Autodesk Fusion 360 part; units mm, degrees
(part 3 of 7)
ref_plane "WorkPlane1" through (0, 0, 65.5) normal (0, 0, 1) x (1, 0, 0) in component "front right crossmember backing plate"
sketch "New stock profile (16)" plane through (0, 0, 65.5) normal (0, 0, 1) x (1, 0, 0) in component "front right crossmember backing plate"
  line L0 (103.6, -314.6) -> (154.4, -314.6)
  line L1 (154.4, -314.6) -> (154.4, -308.25)
  line L2 (154.4, -308.25) -> (103.6, -308.25)
  line L3 (103.6, -308.25) -> (103.6, -314.6)
extrude "New 1'''''''''''''''" add sketch "New stock profile (16)" along normal blind 63.5 separate body makes body 142 in component "front right crossmember backing plate"
ref_plane "WorkPlane1" through (0, 0, 65.5) normal (0, 0, 1) x (1, 0, 0) in component "front left crossmember backing plate"
sketch "New stock profile (17)" plane through (0, 0, 65.5) normal (0, 0, 1) x (1, 0, 0) in component "front left crossmember backing plate"
  line L0 (103.6, 308.25) -> (154.4, 308.25)
  line L1 (154.4, 308.25) -> (154.4, 314.6)
  line L2 (154.4, 314.6) -> (103.6, 314.6)
  line L3 (103.6, 314.6) -> (103.6, 308.25)
extrude "New 1''''''''''''''''" add sketch "New stock profile (17)" along normal blind 63.5 separate body makes body 143 in component "front left crossmember backing plate"
ref_plane "WorkPlane1" through (0, 0, -8.47) normal (0, 0, 1) x (1, 0, 0) in component "front left module tab spacer 1"
sketch "New stock profile (18)" plane through (0, 0, -8.47) normal (0, 0, 1) x (1, 0, 0) in component "front left module tab spacer 1"
  line L0 (-20.7, -14.55) -> (15, -14.55)
  line L1 (15, -14.55) -> (15, 11.55)
  line L2 (15, 11.55) -> (-20.7, 11.55)
  line L3 (-20.7, 11.55) -> (-20.7, -14.55)
extrude "New 1'''''''''''''''''" add sketch "New stock profile (18)" along normal blind 50.8 separate body makes body 144 in component "front left module tab spacer 1"
ref_plane "WorkPlane2" through (0, 0, -10.22) normal (0, 0, 1) x (1, 0, 0) in component "front left module tab spacer 1"
sketch "Cut stock profile (17)" plane through (0, 0, -10.22) normal (0, 0, 1) x (1, 0, 0) in component "front left module tab spacer 1"
  circle A0 centre (9.85, -6.3) radius 2.65
extrude "Cut 2''''''''" cut sketch "Cut stock profile (17)" along normal blind 54 bodies 144 in component "front left module tab spacer 1"
ref_plane "WorkPlane3" through (0, 0, -10.22) normal (0, 0, 1) x (1, 0, 0) in component "front left module tab spacer 1"
sketch "Cut stock profile (1) (6)" plane through (0, 0, -10.22) normal (0, 0, 1) x (1, 0, 0) in component "front left module tab spacer 1"
  circle A0 centre (-15.55, -6.3) radius 2.65
extrude "Cut 3" cut sketch "Cut stock profile (1) (6)" along normal blind 54 bodies 144 in component "front left module tab spacer 1"
ref_plane "WorkPlane4" through (0, 12.55, 0) normal (0, 1, 0) x (0, 0, 1) in component "front left module tab spacer 1"
sketch "Cut stock profile (2) (6)" plane through (0, 12.55, 0) normal (0, 1, 0) x (1, 0, 0) in component "front left module tab spacer 1"
  circle A0 centre (-2.85, -5.78) radius 3.25
extrude "Cut 4" [suppressed] in component "left perimeter tube"
extrude "Extrude7" cut sketch "Cut stock profile (2) (6)" against normal blind 28.1 bodies 144 in component "front left module tab spacer 1"
ref_plane "WorkPlane5" through (0, 12.55, 0) normal (0, 1, 0) x (0, 0, 1) in component "front left module tab spacer 1"
sketch "Cut stock profile (3) (4)" plane through (0, 12.55, 0) normal (0, 1, 0) x (1, 0, 0) in component "front left module tab spacer 1"
  circle A0 centre (-2.85, -26.78) radius 3.25
extrude "Cut 5 (1)" [suppressed] in component "left perimeter tube"
extrude "Extrude8" cut sketch "Cut stock profile (3) (4)" against normal blind 28.1 bodies 144 in component "front left module tab spacer 1"
ref_plane "WorkPlane6" through (0, 12.55, 0) normal (0, 1, 0) x (0, 0, 1) in component "front left module tab spacer 1"
sketch "Cut stock profile (4) (4)" plane through (0, 12.55, 0) normal (0, 1, 0) x (1, 0, 0) in component "front left module tab spacer 1"
  circle A0 centre (9.2, -16.93) radius 5.35
extrude "Cut 6" [suppressed] in component "left perimeter tube"
extrude "Extrude9" cut sketch "Cut stock profile (4) (4)" against normal blind 28.1 bodies 144 in component "front left module tab spacer 1"
ref_plane "WorkPlane7" through (0, 12.55, 0) normal (0, 1, 0) x (0, 0, 1) in component "front left module tab spacer 1"
sketch "Cut stock profile (5) (2)" plane through (0, 12.55, 0) normal (0, 1, 0) x (1, 0, 0) in component "front left module tab spacer 1"
  circle A0 centre (-14.9, -16.93) radius 5.35
extrude "Cut 7" [suppressed] in component "left perimeter tube"
extrude "Extrude10" cut sketch "Cut stock profile (5) (2)" against normal blind 28.1 bodies 144 in component "front left module tab spacer 1"
ref_plane "WorkPlane1" through (0, 0, -8.47) normal (0, 0, 1) x (1, 0, 0) in component "front left module tab spacer 2"
sketch "New stock profile (19)" plane through (0, 0, -8.47) normal (0, 0, 1) x (1, 0, 0) in component "front left module tab spacer 2"
  line L0 (-14.55, -20.7) -> (11.55, -20.7)
  line L1 (11.55, -20.7) -> (11.55, 15)
  line L2 (11.55, 15) -> (-14.55, 15)
  line L3 (-14.55, 15) -> (-14.55, -20.7)
extrude "New 1''''''''''''''''''" add sketch "New stock profile (19)" along normal blind 50.8 separate body makes body 145 in component "front left module tab spacer 2"
ref_plane "WorkPlane2" through (0, 0, -10.22) normal (0, 0, 1) x (1, 0, 0) in component "front left module tab spacer 2"
sketch "Cut stock profile (18)" plane through (0, 0, -10.22) normal (0, 0, 1) x (1, 0, 0) in component "front left module tab spacer 2"
  circle A0 centre (-6.3, 9.85) radius 2.65
extrude "Cut 2'''''''''" cut sketch "Cut stock profile (18)" along normal blind 54 bodies 145 in component "front left module tab spacer 2"
ref_plane "WorkPlane3" through (0, 0, -10.22) normal (0, 0, 1) x (1, 0, 0) in component "front left module tab spacer 2"
sketch "Cut stock profile (1) (7)" plane through (0, 0, -10.22) normal (0, 0, 1) x (1, 0, 0) in component "front left module tab spacer 2"
  circle A0 centre (-6.3, -15.55) radius 2.65
extrude "Cut 3'" cut sketch "Cut stock profile (1) (7)" along normal blind 54 bodies 145 in component "front left module tab spacer 2"
ref_plane "WorkPlane4" through (12.55, 0, 0) normal (1, 0, 0) x (0, 1, 0) in component "front left module tab spacer 2"
sketch "Cut stock profile (2) (7)" plane through (12.55, 0, 0) normal (1, 0, 0) x (0, 0, -1) in component "front left module tab spacer 2"
  circle A0 centre (-5.78, -2.85) radius 3.25
extrude "Cut 4'" [suppressed] in component "left front return"
extrude "Extrude7'" cut sketch "Cut stock profile (2) (7)" against normal blind 28.1 bodies 145 in component "front left module tab spacer 2"
ref_plane "WorkPlane5" through (12.55, 0, 0) normal (1, 0, 0) x (0, 1, 0) in component "front left module tab spacer 2"
sketch "Cut stock profile (3) (5)" plane through (12.55, 0, 0) normal (1, 0, 0) x (0, 0, -1) in component "front left module tab spacer 2"
  circle A0 centre (-26.78, -2.85) radius 3.25
extrude "Cut 5" [suppressed] in component "left front return"
extrude "Extrude8'" cut sketch "Cut stock profile (3) (5)" against normal blind 28.1 bodies 145 in component "front left module tab spacer 2"
ref_plane "WorkPlane6" through (12.55, 0, 0) normal (1, 0, 0) x (0, 1, 0) in component "front left module tab spacer 2"
sketch "Cut stock profile (4) (5)" plane through (12.55, 0, 0) normal (1, 0, 0) x (0, 0, -1) in component "front left module tab spacer 2"
  circle A0 centre (-16.93, 9.2) radius 5.35
extrude "Cut 6'" [suppressed] in component "left front return"
extrude "Extrude9'" cut sketch "Cut stock profile (4) (5)" against normal blind 28.1 bodies 145 in component "front left module tab spacer 2"
ref_plane "WorkPlane7" through (12.55, 0, 0) normal (1, 0, 0) x (0, 1, 0) in component "front left module tab spacer 2"
sketch "Cut stock profile (5) (3)" plane through (12.55, 0, 0) normal (1, 0, 0) x (0, 0, -1) in component "front left module tab spacer 2"
  circle A0 centre (-16.93, -14.9) radius 5.35
extrude "Cut 7'" [suppressed] in component "left front return"
extrude "Extrude10'" cut sketch "Cut stock profile (5) (3)" against normal blind 28.1 bodies 145 in component "front left module tab spacer 2"
ref_plane "WorkPlane1" through (0, 0, -8.47) normal (0, 0, 1) x (1, 0, 0) in component "front right module tab spacer 1"
sketch "New stock profile (20)" plane through (0, 0, -8.47) normal (0, 0, 1) x (1, 0, 0) in component "front right module tab spacer 1"
  line L0 (-14.55, -15) -> (11.55, -15)
  line L1 (11.55, -15) -> (11.55, 20.7)
  line L2 (11.55, 20.7) -> (-14.55, 20.7)
  line L3 (-14.55, 20.7) -> (-14.55, -15)
extrude "New 1'''''''''''''''''''" add sketch "New stock profile (20)" along normal blind 50.8 separate body makes body 146 in component "front right module tab spacer 1"
ref_plane "WorkPlane2" through (0, 0, -10.22) normal (0, 0, 1) x (1, 0, 0) in component "front right module tab spacer 1"
sketch "Cut stock profile (19)" plane through (0, 0, -10.22) normal (0, 0, 1) x (1, 0, 0) in component "front right module tab spacer 1"
  circle A0 centre (-6.3, -9.85) radius 2.65
extrude "Cut 2''''''''''" cut sketch "Cut stock profile (19)" along normal blind 54 bodies 146 in component "front right module tab spacer 1"
ref_plane "WorkPlane3" through (0, 0, -10.22) normal (0, 0, 1) x (1, 0, 0) in component "front right module tab spacer 1"
sketch "Cut stock profile (1) (8)" plane through (0, 0, -10.22) normal (0, 0, 1) x (1, 0, 0) in component "front right module tab spacer 1"
  circle A0 centre (-6.3, 15.55) radius 2.65
extrude "Cut 3''" cut sketch "Cut stock profile (1) (8)" along normal blind 54 bodies 146 in component "front right module tab spacer 1"
ref_plane "WorkPlane4" through (12.55, 0, 0) normal (1, 0, 0) x (0, 1, 0) in component "front right module tab spacer 1"
sketch "Cut stock profile (2) (8)" plane through (12.55, 0, 0) normal (1, 0, 0) x (0, 0, -1) in component "front right module tab spacer 1"
  circle A0 centre (-5.78, 2.85) radius 3.25
extrude "Cut 4''" [suppressed] in component "right front return"
extrude "Extrude7''" cut sketch "Cut stock profile (2) (8)" against normal blind 28.1 bodies 146 in component "front right module tab spacer 1"
ref_plane "WorkPlane5" through (12.55, 0, 0) normal (1, 0, 0) x (0, 1, 0) in component "front right module tab spacer 1"
sketch "Cut stock profile (3) (6)" plane through (12.55, 0, 0) normal (1, 0, 0) x (0, 0, -1) in component "front right module tab spacer 1"
  circle A0 centre (-26.78, 2.85) radius 3.25
extrude "Cut 5'" [suppressed] in component "right front return"
extrude "Extrude8''" cut sketch "Cut stock profile (3) (6)" against normal blind 28.1 bodies 146 in component "front right module tab spacer 1"
ref_plane "WorkPlane6" through (12.55, 0, 0) normal (1, 0, 0) x (0, 1, 0) in component "front right module tab spacer 1"
sketch "Cut stock profile (4) (6)" plane through (12.55, 0, 0) normal (1, 0, 0) x (0, 0, -1) in component "front right module tab spacer 1"
  circle A0 centre (-16.93, -9.2) radius 5.35
extrude "Cut 6''" [suppressed] in component "right front return"
extrude "Extrude9''" cut sketch "Cut stock profile (4) (6)" against normal blind 28.1 bodies 146 in component "front right module tab spacer 1"
ref_plane "WorkPlane7" through (12.55, 0, 0) normal (1, 0, 0) x (0, 1, 0) in component "front right module tab spacer 1"
sketch "Cut stock profile (5) (4)" plane through (12.55, 0, 0) normal (1, 0, 0) x (0, 0, -1) in component "front right module tab spacer 1"
  circle A0 centre (-16.93, 14.9) radius 5.35
extrude "Cut 7''" [suppressed] in component "right front return"
extrude "Extrude10''" cut sketch "Cut stock profile (5) (4)" against normal blind 28.1 bodies 146 in component "front right module tab spacer 1"
ref_plane "WorkPlane1" through (0, 0, -8.47) normal (0, 0, 1) x (1, 0, 0) in component "front right module tab spacer 2"
sketch "New stock profile (21)" plane through (0, 0, -8.47) normal (0, 0, 1) x (1, 0, 0) in component "front right module tab spacer 2"
  line L0 (-20.7, -11.55) -> (15, -11.55)
  line L1 (15, -11.55) -> (15, 14.55)
  line L2 (15, 14.55) -> (-20.7, 14.55)
  line L3 (-20.7, 14.55) -> (-20.7, -11.55)
extrude "New 1''''''''''''''''''''" add sketch "New stock profile (21)" along normal blind 50.8 separate body makes body 147 in component "front right module tab spacer 2"
ref_plane "WorkPlane2" through (0, 0, -10.22) normal (0, 0, 1) x (1, 0, 0) in component "front right module tab spacer 2"
sketch "Cut stock profile (20)" plane through (0, 0, -10.22) normal (0, 0, 1) x (1, 0, 0) in component "front right module tab spacer 2"
  circle A0 centre (9.85, 6.3) radius 2.65
extrude "Cut 2'''''''''''" cut sketch "Cut stock profile (20)" along normal blind 54 bodies 147 in component "front right module tab spacer 2"
ref_plane "WorkPlane3" through (0, 0, -10.22) normal (0, 0, 1) x (1, 0, 0) in component "front right module tab spacer 2"
sketch "Cut stock profile (1) (9)" plane through (0, 0, -10.22) normal (0, 0, 1) x (1, 0, 0) in component "front right module tab spacer 2"
  circle A0 centre (-15.55, 6.3) radius 2.65
extrude "Cut 3'''" cut sketch "Cut stock profile (1) (9)" along normal blind 54 bodies 147 in component "front right module tab spacer 2"
ref_plane "WorkPlane4" through (0, -12.55, 0) normal (0, 1, 0) x (0, 0, 1) in component "front right module tab spacer 2"
sketch "Cut stock profile (2) (9)" plane through (0, -12.55, 0) normal (0, 1, 0) x (1, 0, 0) in component "front right module tab spacer 2"
  circle A0 centre (-2.85, -5.78) radius 3.25
extrude "Cut 4'''" [suppressed] in component "right perimeter tube"
extrude "Extrude7'''" cut sketch "Cut stock profile (2) (9)" along normal blind 28.1 bodies 147 in component "front right module tab spacer 2"
ref_plane "WorkPlane5" through (0, -12.55, 0) normal (0, 1, 0) x (0, 0, 1) in component "front right module tab spacer 2"
sketch "Cut stock profile (3) (7)" plane through (0, -12.55, 0) normal (0, 1, 0) x (1, 0, 0) in component "front right module tab spacer 2"
  circle A0 centre (-2.85, -26.78) radius 3.25
extrude "Cut 5 (1)'" [suppressed] in component "right perimeter tube"
extrude "Extrude8'''" cut sketch "Cut stock profile (3) (7)" along normal blind 28.1 bodies 147 in component "front right module tab spacer 2"
ref_plane "WorkPlane6" through (0, -12.55, 0) normal (0, 1, 0) x (0, 0, 1) in component "front right module tab spacer 2"
sketch "Cut stock profile (4) (7)" plane through (0, -12.55, 0) normal (0, 1, 0) x (1, 0, 0) in component "front right module tab spacer 2"
  circle A0 centre (9.2, -16.93) radius 5.35
extrude "Cut 6'''" [suppressed] in component "right perimeter tube"
extrude "Extrude9'''" cut sketch "Cut stock profile (4) (7)" along normal blind 28.1 bodies 147 in component "front right module tab spacer 2"
ref_plane "WorkPlane7" through (0, -12.55, 0) normal (0, 1, 0) x (0, 0, 1) in component "front right module tab spacer 2"
sketch "Cut stock profile (5) (5)" plane through (0, -12.55, 0) normal (0, 1, 0) x (1, 0, 0) in component "front right module tab spacer 2"
  circle A0 centre (-14.9, -16.93) radius 5.35
extrude "Cut 7'''" [suppressed] in component "right perimeter tube"
extrude "Extrude10'''" cut sketch "Cut stock profile (5) (5)" along normal blind 28.1 bodies 147 in component "front right module tab spacer 2"
ref_plane "WorkPlane1" through (0, 0, -8.47) normal (0, 0, 1) x (1, 0, 0) in component "rear left module tab spacer 1"
sketch "New stock profile (22)" plane through (0, 0, -8.47) normal (0, 0, 1) x (1, 0, 0) in component "rear left module tab spacer 1"
  line L0 (-11.55, -20.7) -> (14.55, -20.7)
  line L1 (14.55, -20.7) -> (14.55, 15)
  line L2 (14.55, 15) -> (-11.55, 15)
  line L3 (-11.55, 15) -> (-11.55, -20.7)
extrude "New 1'''''''''''''''''''''" add sketch "New stock profile (22)" along normal blind 50.8 separate body makes body 148 in component "rear left module tab spacer 1"
ref_plane "WorkPlane2" through (0, 0, -10.22) normal (0, 0, 1) x (1, 0, 0) in component "rear left module tab spacer 1"
sketch "Cut stock profile (21)" plane through (0, 0, -10.22) normal (0, 0, 1) x (1, 0, 0) in component "rear left module tab spacer 1"
  circle A0 centre (6.3, 9.85) radius 2.65
extrude "Cut 2''''''''''''" cut sketch "Cut stock profile (21)" along normal blind 54 bodies 148 in component "rear left module tab spacer 1"
ref_plane "WorkPlane3" through (0, 0, -10.22) normal (0, 0, 1) x (1, 0, 0) in component "rear left module tab spacer 1"
sketch "Cut stock profile (1) (10)" plane through (0, 0, -10.22) normal (0, 0, 1) x (1, 0, 0) in component "rear left module tab spacer 1"
  circle A0 centre (6.3, -15.55) radius 2.65
extrude "Cut 3''''" cut sketch "Cut stock profile (1) (10)" along normal blind 54 bodies 148 in component "rear left module tab spacer 1"
ref_plane "WorkPlane4" through (-12.55, 0, 0) normal (1, 0, 0) x (0, 1, 0) in component "rear left module tab spacer 1"
sketch "Cut stock profile (2) (10)" plane through (-12.55, 0, 0) normal (1, 0, 0) x (0, 0, -1) in component "rear left module tab spacer 1"
  circle A0 centre (-5.78, -2.85) radius 3.25
extrude "Cut 4''''" [suppressed] in component "rear perimeter tube"
extrude "Extrude7''''" cut sketch "Cut stock profile (2) (10)" along normal blind 28.1 bodies 148 in component "rear left module tab spacer 1"
ref_plane "WorkPlane5" through (-12.55, 0, 0) normal (1, 0, 0) x (0, 1, 0) in component "rear left module tab spacer 1"
sketch "Cut stock profile (3) (8)" plane through (-12.55, 0, 0) normal (1, 0, 0) x (0, 0, -1) in component "rear left module tab spacer 1"
  circle A0 centre (-26.78, -2.85) radius 3.25
extrude "Cut 5 (1)''" [suppressed] in component "rear perimeter tube"
extrude "Extrude8''''" cut sketch "Cut stock profile (3) (8)" along normal blind 28.1 bodies 148 in component "rear left module tab spacer 1"
ref_plane "WorkPlane6" through (-12.55, 0, 0) normal (1, 0, 0) x (0, 1, 0) in component "rear left module tab spacer 1"
sketch "Cut stock profile (4) (8)" plane through (-12.55, 0, 0) normal (1, 0, 0) x (0, 0, -1) in component "rear left module tab spacer 1"
  circle A0 centre (-16.93, 9.2) radius 5.35
extrude "Cut 6 (1)" [suppressed] in component "rear perimeter tube"
extrude "Extrude9''''" cut sketch "Cut stock profile (4) (8)" along normal blind 28.1 bodies 148 in component "rear left module tab spacer 1"
ref_plane "WorkPlane7" through (-12.55, 0, 0) normal (1, 0, 0) x (0, 1, 0) in component "rear left module tab spacer 1"
sketch "Cut stock profile (5) (6)" plane through (-12.55, 0, 0) normal (1, 0, 0) x (0, 0, -1) in component "rear left module tab spacer 1"
  circle A0 centre (-16.93, -14.9) radius 5.35
extrude "Cut 7''''" [suppressed] in component "rear perimeter tube"
extrude "Extrude10''''" cut sketch "Cut stock profile (5) (6)" along normal blind 28.1 bodies 148 in component "rear left module tab spacer 1"
ref_plane "WorkPlane1" through (0, 0, -8.47) normal (0, 0, 1) x (1, 0, 0) in component "rear left module tab spacer 2"
sketch "New stock profile (23)" plane through (0, 0, -8.47) normal (0, 0, 1) x (1, 0, 0) in component "rear left module tab spacer 2"
  line L0 (-15, -14.55) -> (20.7, -14.55)
  line L1 (20.7, -14.55) -> (20.7, 11.55)
  line L2 (20.7, 11.55) -> (-15, 11.55)
  line L3 (-15, 11.55) -> (-15, -14.55)
extrude "New 1''''''''''''''''''''''" add sketch "New stock profile (23)" along normal blind 50.8 separate body makes body 149 in component "rear left module tab spacer 2"
ref_plane "WorkPlane2" through (0, 0, -10.22) normal (0, 0, 1) x (1, 0, 0) in component "rear left module tab spacer 2"
sketch "Cut stock profile (22)" plane through (0, 0, -10.22) normal (0, 0, 1) x (1, 0, 0) in component "rear left module tab spacer 2"
  circle A0 centre (-9.85, -6.3) radius 2.65
extrude "Cut 2'''''''''''''" cut sketch "Cut stock profile (22)" along normal blind 54 bodies 149 in component "rear left module tab spacer 2"
ref_plane "WorkPlane3" through (0, 0, -10.22) normal (0, 0, 1) x (1, 0, 0) in component "rear left module tab spacer 2"
sketch "Cut stock profile (1) (11)" plane through (0, 0, -10.22) normal (0, 0, 1) x (1, 0, 0) in component "rear left module tab spacer 2"
  circle A0 centre (15.55, -6.3) radius 2.65
extrude "Cut 3'''''" cut sketch "Cut stock profile (1) (11)" along normal blind 54 bodies 149 in component "rear left module tab spacer 2"
ref_plane "WorkPlane4" through (0, 12.55, 0) normal (0, 1, 0) x (0, 0, 1) in component "rear left module tab spacer 2"
sketch "Cut stock profile (2) (11)" plane through (0, 12.55, 0) normal (0, 1, 0) x (1, 0, 0) in component "rear left module tab spacer 2"
  circle A0 centre (2.85, -5.78) radius 3.25
extrude "Cut 4 (1)" [suppressed] in component "left perimeter tube"
extrude "Extrude7'''''" cut sketch "Cut stock profile (2) (11)" against normal blind 28.1 bodies 149 in component "rear left module tab spacer 2"
ref_plane "WorkPlane5" through (0, 12.55, 0) normal (0, 1, 0) x (0, 0, 1) in component "rear left module tab spacer 2"
sketch "Cut stock profile (3) (9)" plane through (0, 12.55, 0) normal (0, 1, 0) x (1, 0, 0) in component "rear left module tab spacer 2"
  circle A0 centre (2.85, -26.78) radius 3.25
extrude "Cut 5''" [suppressed] in component "left perimeter tube"
extrude "Extrude8'''''" cut sketch "Cut stock profile (3) (9)" against normal blind 28.1 bodies 149 in component "rear left module tab spacer 2"
ref_plane "WorkPlane6" through (0, 12.55, 0) normal (0, 1, 0) x (0, 0, 1) in component "rear left module tab spacer 2"
sketch "Cut stock profile (4) (9)" plane through (0, 12.55, 0) normal (0, 1, 0) x (1, 0, 0) in component "rear left module tab spacer 2"
  circle A0 centre (-9.2, -16.93) radius 5.35
extrude "Cut 6 (1)'" [suppressed] in component "left perimeter tube"
extrude "Extrude9'''''" cut sketch "Cut stock profile (4) (9)" against normal blind 28.1 bodies 149 in component "rear left module tab spacer 2"
ref_plane "WorkPlane7" through (0, 12.55, 0) normal (0, 1, 0) x (0, 0, 1) in component "rear left module tab spacer 2"
sketch "Cut stock profile (5) (7)" plane through (0, 12.55, 0) normal (0, 1, 0) x (1, 0, 0) in component "rear left module tab spacer 2"
  circle A0 centre (14.9, -16.93) radius 5.35
extrude "Cut 7 (1)" [suppressed] in component "left perimeter tube"
extrude "Extrude10'''''" cut sketch "Cut stock profile (5) (7)" against normal blind 28.1 bodies 149 in component "rear left module tab spacer 2"
ref_plane "WorkPlane1" through (0, 0, -8.47) normal (0, 0, 1) x (1, 0, 0) in component "rear right module tab spacer 1"
sketch "New stock profile (24)" plane through (0, 0, -8.47) normal (0, 0, 1) x (1, 0, 0) in component "rear right module tab spacer 1"
  line L0 (-15, -11.55) -> (20.7, -11.55)
  line L1 (20.7, -11.55) -> (20.7, 14.55)
  line L2 (20.7, 14.55) -> (-15, 14.55)
  line L3 (-15, 14.55) -> (-15, -11.55)
extrude "New 1'''''''''''''''''''''''" add sketch "New stock profile (24)" along normal blind 50.8 separate body makes body 150 in component "rear right module tab spacer 1"
ref_plane "WorkPlane2" through (0, 0, -10.22) normal (0, 0, 1) x (1, 0, 0) in component "rear right module tab spacer 1"
sketch "Cut stock profile (23)" plane through (0, 0, -10.22) normal (0, 0, 1) x (1, 0, 0) in component "rear right module tab spacer 1"
  circle A0 centre (-9.85, 6.3) radius 2.65
extrude "Cut 2''''''''''''''" cut sketch "Cut stock profile (23)" along normal blind 54 bodies 150 in component "rear right module tab spacer 1"
ref_plane "WorkPlane3" through (0, 0, -10.22) normal (0, 0, 1) x (1, 0, 0) in component "rear right module tab spacer 1"
sketch "Cut stock profile (1) (12)" plane through (0, 0, -10.22) normal (0, 0, 1) x (1, 0, 0) in component "rear right module tab spacer 1"
  circle A0 centre (15.55, 6.3) radius 2.65
extrude "Cut 3''''''" cut sketch "Cut stock profile (1) (12)" along normal blind 54 bodies 150 in component "rear right module tab spacer 1"
ref_plane "WorkPlane4" through (0, -12.55, 0) normal (0, 1, 0) x (0, 0, 1) in component "rear right module tab spacer 1"
sketch "Cut stock profile (2) (12)" plane through (0, -12.55, 0) normal (0, 1, 0) x (1, 0, 0) in component "rear right module tab spacer 1"
  circle A0 centre (2.85, -5.78) radius 3.25
extrude "Cut 4 (1)'" [suppressed] in component "right perimeter tube"
extrude "Extrude7''''''" cut sketch "Cut stock profile (2) (12)" along normal blind 28.1 bodies 150 in component "rear right module tab spacer 1"
ref_plane "WorkPlane5" through (0, -12.55, 0) normal (0, 1, 0) x (0, 0, 1) in component "rear right module tab spacer 1"
sketch "Cut stock profile (3) (10)" plane through (0, -12.55, 0) normal (0, 1, 0) x (1, 0, 0) in component "rear right module tab spacer 1"
  circle A0 centre (2.85, -26.78) radius 3.25
extrude "Cut 5'''" [suppressed] in component "right perimeter tube"
extrude "Extrude8''''''" cut sketch "Cut stock profile (3) (10)" along normal blind 28.1 bodies 150 in component "rear right module tab spacer 1"
ref_plane "WorkPlane6" through (0, -12.55, 0) normal (0, 1, 0) x (0, 0, 1) in component "rear right module tab spacer 1"
sketch "Cut stock profile (4) (10)" plane through (0, -12.55, 0) normal (0, 1, 0) x (1, 0, 0) in component "rear right module tab spacer 1"
  circle A0 centre (-9.2, -16.93) radius 5.35
extrude "Cut 6 (1)''" [suppressed] in component "right perimeter tube"
extrude "Extrude9''''''" cut sketch "Cut stock profile (4) (10)" along normal blind 28.1 bodies 150 in component "rear right module tab spacer 1"
ref_plane "WorkPlane7" through (0, -12.55, 0) normal (0, 1, 0) x (0, 0, 1) in component "rear right module tab spacer 1"
sketch "Cut stock profile (5) (8)" plane through (0, -12.55, 0) normal (0, 1, 0) x (1, 0, 0) in component "rear right module tab spacer 1"
  circle A0 centre (14.9, -16.93) radius 5.35
extrude "Cut 7 (1)'" [suppressed] in component "right perimeter tube"
extrude "Extrude10''''''" cut sketch "Cut stock profile (5) (8)" along normal blind 28.1 bodies 150 in component "rear right module tab spacer 1"
ref_plane "WorkPlane1" through (0, 0, -8.47) normal (0, 0, 1) x (1, 0, 0) in component "rear right module tab spacer 2"
sketch "New stock profile (25)" plane through (0, 0, -8.47) normal (0, 0, 1) x (1, 0, 0) in component "rear right module tab spacer 2"
  line L0 (-11.55, -15) -> (14.55, -15)
  line L1 (14.55, -15) -> (14.55, 20.7)
  line L2 (14.55, 20.7) -> (-11.55, 20.7)
  line L3 (-11.55, 20.7) -> (-11.55, -15)
extrude "New 1''''''''''''''''''''''''" add sketch "New stock profile (25)" along normal blind 50.8 separate body makes body 151 in component "rear right module tab spacer 2"
ref_plane "WorkPlane2" through (0, 0, -10.22) normal (0, 0, 1) x (1, 0, 0) in component "rear right module tab spacer 2"
sketch "Cut stock profile (24)" plane through (0, 0, -10.22) normal (0, 0, 1) x (1, 0, 0) in component "rear right module tab spacer 2"
  circle A0 centre (6.3, -9.85) radius 2.65
extrude "Cut 2'''''''''''''''" cut sketch "Cut stock profile (24)" along normal blind 54 bodies 151 in component "rear right module tab spacer 2"
ref_plane "WorkPlane3" through (0, 0, -10.22) normal (0, 0, 1) x (1, 0, 0) in component "rear right module tab spacer 2"
sketch "Cut stock profile (1) (13)" plane through (0, 0, -10.22) normal (0, 0, 1) x (1, 0, 0) in component "rear right module tab spacer 2"
  circle A0 centre (6.3, 15.55) radius 2.65
extrude "Cut 3'''''''" cut sketch "Cut stock profile (1) (13)" along normal blind 54 bodies 151 in component "rear right module tab spacer 2"
ref_plane "WorkPlane4" through (-12.55, 0, 0) normal (1, 0, 0) x (0, 1, 0) in component "rear right module tab spacer 2"
sketch "Cut stock profile (2) (13)" plane through (-12.55, 0, 0) normal (1, 0, 0) x (0, 0, -1) in component "rear right module tab spacer 2"
  circle A0 centre (-5.78, 2.85) radius 3.25
extrude "Cut 4 (1)''" [suppressed] in component "rear perimeter tube"
extrude "Extrude7'''''''" cut sketch "Cut stock profile (2) (13)" along normal blind 28.1 bodies 151 in component "rear right module tab spacer 2"
ref_plane "WorkPlane5" through (-12.55, 0, 0) normal (1, 0, 0) x (0, 1, 0) in component "rear right module tab spacer 2"
sketch "Cut stock profile (3) (11)" plane through (-12.55, 0, 0) normal (1, 0, 0) x (0, 0, -1) in component "rear right module tab spacer 2"
  circle A0 centre (-26.78, 2.85) radius 3.25
extrude "Cut 5''''" [suppressed] in component "rear perimeter tube"
extrude "Extrude8'''''''" cut sketch "Cut stock profile (3) (11)" along normal blind 28.1 bodies 151 in component "rear right module tab spacer 2"
ref_plane "WorkPlane6" through (-12.55, 0, 0) normal (1, 0, 0) x (0, 1, 0) in component "rear right module tab spacer 2"
sketch "Cut stock profile (4) (11)" plane through (-12.55, 0, 0) normal (1, 0, 0) x (0, 0, -1) in component "rear right module tab spacer 2"
  circle A0 centre (-16.93, -9.2) radius 5.35
extrude "Cut 6''''" [suppressed] in component "rear perimeter tube"
extrude "Extrude9'''''''" cut sketch "Cut stock profile (4) (11)" along normal blind 28.1 bodies 151 in component "rear right module tab spacer 2"
ref_plane "WorkPlane7" through (-12.55, 0, 0) normal (1, 0, 0) x (0, 1, 0) in component "rear right module tab spacer 2"
sketch "Cut stock profile (5) (9)" plane through (-12.55, 0, 0) normal (1, 0, 0) x (0, 0, -1) in component "rear right module tab spacer 2"
  circle A0 centre (-16.93, 14.9) radius 5.35
extrude "Cut 7 (1)''" [suppressed] in component "rear perimeter tube"
extrude "Extrude10'''''''" cut sketch "Cut stock profile (5) (9)" along normal blind 28.1 bodies 151 in component "rear right module tab spacer 2"
ref_plane "WorkPlane1" through (0, 330.6, 0) normal (0, 1, 0) x (0, 0, 1) in component "front left rail mount 1-1 weld boss"
sketch "New stock profile (26)" plane through (0, 330.6, 0) normal (0, 1, 0) x (1, 0, 0) in component "front left rail mount 1-1 weld boss"
  circle A0 centre (195.15, -84.1) radius 6.5
  circle A1 centre (195.15, -84.1) radius 2.5
extrude "New 1'''''''''''''''''''''''''" add sketch "New stock profile (26)" against normal blind 16 separate body makes body 152 in component "front left rail mount 1-1 weld boss"
ref_plane "WorkPlane1" through (0, 328.5, 0) normal (0, 1, 0) x (0, 0, 1) in component "front left rail mount 1-1 M6 cap screw"
sketch "New stock profile (27)" plane through (0, 328.5, 0) normal (0, 1, 0) x (1, 0, 0) in component "front left rail mount 1-1 M6 cap screw"
  circle A0 centre (195.15, -84.1) radius 3
extrude "New 1''''''''''''''''''''''''''" add sketch "New stock profile (27)" against normal blind 40 separate body makes body 153 in component "front left rail mount 1-1 M6 cap screw"
ref_plane "WorkPlane2" through (0, 288.5, 0) normal (0, 1, 0) x (0, 0, 1) in component "front left rail mount 1-1 M6 cap screw"
sketch "Join stock profile" plane through (0, 288.5, 0) normal (0, 1, 0) x (1, 0, 0) in component "front left rail mount 1-1 M6 cap screw"
  circle A0 centre (195.15, -84.1) radius 5
extrude "Join 2" add sketch "Join stock profile" against normal blind 6 bodies 153 in component "front left rail mount 1-1 M6 cap screw"
ref_plane "WorkPlane3" through (0, 282.49, 0) normal (0, 1, 0) x (0, 0, 1) in component "front left rail mount 1-1 M6 cap screw"
sketch "Cut stock profile (25)" plane through (0, 282.49, 0) normal (0, 1, 0) x (1, 0, 0) in component "front left rail mount 1-1 M6 cap screw"
  line L0 (192.2632, -84.1) -> (193.7066, -86.6)
  line L1 (193.7066, -86.6) -> (196.5934, -86.6)
  line L2 (196.5934, -86.6) -> (198.0368, -84.1)
  line L3 (198.0368, -84.1) -> (196.5934, -81.6)
  line L4 (196.5934, -81.6) -> (193.7066, -81.6)
  line L5 (193.7066, -81.6) -> (192.2632, -84.1)
extrude "Cut 3''''''''" cut sketch "Cut stock profile (25)" along normal blind 3.01 bodies 153 in component "front left rail mount 1-1 M6 cap screw"
ref_plane "WorkPlane1" through (0, 330.6, 0) normal (0, 1, 0) x (0, 0, 1) in component "front left rail mount 1-2 weld boss"
sketch "New stock profile (28)" plane through (0, 330.6, 0) normal (0, 1, 0) x (1, 0, 0) in component "front left rail mount 1-2 weld boss"
  circle A0 centre (195.15, -105.1) radius 6.5
  circle A1 centre (195.15, -105.1) radius 2.5
extrude "New 1'''''''''''''''''''''''''''" add sketch "New stock profile (28)" against normal blind 16 separate body makes body 154 in component "front left rail mount 1-2 weld boss"
ref_plane "WorkPlane1" through (0, 328.5, 0) normal (0, 1, 0) x (0, 0, 1) in component "front left rail mount 1-2 M6 cap screw"
sketch "New stock profile (29)" plane through (0, 328.5, 0) normal (0, 1, 0) x (1, 0, 0) in component "front left rail mount 1-2 M6 cap screw"
  circle A0 centre (195.15, -105.1) radius 3
extrude "New 1''''''''''''''''''''''''''''" add sketch "New stock profile (29)" against normal blind 40 separate body makes body 155 in component "front left rail mount 1-2 M6 cap screw"
ref_plane "WorkPlane2" through (0, 288.5, 0) normal (0, 1, 0) x (0, 0, 1) in component "front left rail mount 1-2 M6 cap screw"
sketch "Join stock profile (2)" plane through (0, 288.5, 0) normal (0, 1, 0) x (1, 0, 0) in component "front left rail mount 1-2 M6 cap screw"
  circle A0 centre (195.15, -105.1) radius 5
extrude "Join 2'" add sketch "Join stock profile (2)" against normal blind 6 bodies 155 in component "front left rail mount 1-2 M6 cap screw"
ref_plane "WorkPlane3" through (0, 282.49, 0) normal (0, 1, 0) x (0, 0, 1) in component "front left rail mount 1-2 M6 cap screw"
sketch "Cut stock profile (26)" plane through (0, 282.49, 0) normal (0, 1, 0) x (1, 0, 0) in component "front left rail mount 1-2 M6 cap screw"
  line L0 (192.2632, -105.1) -> (193.7066, -107.6)
  line L1 (193.7066, -107.6) -> (196.5934, -107.6)
  line L2 (196.5934, -107.6) -> (198.0368, -105.1)
  line L3 (198.0368, -105.1) -> (196.5934, -102.6)
  line L4 (196.5934, -102.6) -> (193.7066, -102.6)
  line L5 (193.7066, -102.6) -> (192.2632, -105.1)
extrude "Cut 3'''''''''" cut sketch "Cut stock profile (26)" along normal blind 3.01 bodies 155 in component "front left rail mount 1-2 M6 cap screw"
ref_plane "WorkPlane1" through (0, 0, 65.5637) normal (0, 0, 1) x (1, 0, 0) in component "front left tab 1-1 socket screw"
sketch "New stock profile (30)" plane through (0, 0, 65.5637) normal (0, 0, 1) x (1, 0, 0) in component "front left tab 1-1 socket screw"
  circle A0 centre (207.85, 296.75) radius 2.413
extrude "New 1'''''''''''''''''''''''''''''" add sketch "New stock profile (30)" along normal blind 69.85 separate body makes body 156 in component "front left tab 1-1 socket screw"
ref_plane "WorkPlane2" through (0, 0, 60.7378) normal (0, 0, 1) x (1, 0, 0) in component "front left tab 1-1 socket screw"
sketch "Join stock profile (3)" plane through (0, 0, 60.7378) normal (0, 0, 1) x (1, 0, 0) in component "front left tab 1-1 socket screw"
  circle A0 centre (207.85, 296.75) radius 3.9624
extrude "Join 2''" add sketch "Join stock profile (3)" along normal blind 4.826 bodies 156 in component "front left tab 1-1 socket screw"
ref_plane "WorkPlane3" through (0, 0, 60.7278) normal (0, 0, 1) x (1, 0, 0) in component "front left tab 1-1 socket screw"
sketch "Cut stock profile (27)" plane through (0, 0, 60.7278) normal (0, 0, 1) x (1, 0, 0) in component "front left tab 1-1 socket screw"
  line L0 (210.1414, 296.75) -> (208.9957, 298.7344)
  line L1 (208.9957, 298.7344) -> (206.7043, 298.7344)
  line L2 (206.7043, 298.7344) -> (205.5586, 296.75)
  line L3 (205.5586, 296.75) -> (206.7043, 294.7656)
  line L4 (206.7043, 294.7656) -> (208.9957, 294.7656)
  line L5 (208.9957, 294.7656) -> (210.1414, 296.75)
extrude "Cut 3''''''''''" cut sketch "Cut stock profile (27)" along normal blind 2.296 bodies 156 in component "front left tab 1-1 socket screw"
ref_plane "WorkPlane1" through (0, 0, 124.3125) normal (0, 0, 1) x (1, 0, 0) in component "front left tab 1-1 locknut"
sketch "New stock profile (31)" plane through (0, 0, 124.3125) normal (0, 0, 1) x (1, 0, 0) in component "front left tab 1-1 locknut"
  line L0 (213.3639, 296.75) -> (210.607, 301.5252)
  line L1 (210.607, 301.5252) -> (205.093, 301.5252)
  line L2 (205.093, 301.5252) -> (202.3361, 296.75)
  line L3 (202.3361, 296.75) -> (205.093, 291.9748)
  line L4 (205.093, 291.9748) -> (210.607, 291.9748)
  line L5 (210.607, 291.9748) -> (213.3639, 296.75)
  circle A0 centre (207.85, 296.75) radius 2.43
extrude "New 1''''''''''''''''''''''''''''''" add sketch "New stock profile (31)" along normal blind 6.3246 separate body makes body 157 in component "front left tab 1-1 locknut"
ref_plane "WorkPlane1" through (0, 0, 65.5637) normal (0, 0, 1) x (1, 0, 0) in component "front left tab 1-2 socket screw"
sketch "New stock profile (32)" plane through (0, 0, 65.5637) normal (0, 0, 1) x (1, 0, 0) in component "front left tab 1-2 socket screw"
  circle A0 centre (182.45, 296.75) radius 2.413
extrude "New 1'''''''''''''''''''''''''''''''" add sketch "New stock profile (32)" along normal blind 69.85 separate body makes body 158 in component "front left tab 1-2 socket screw"
ref_plane "WorkPlane2" through (0, 0, 60.7378) normal (0, 0, 1) x (1, 0, 0) in component "front left tab 1-2 socket screw"
sketch "Join stock profile (4)" plane through (0, 0, 60.7378) normal (0, 0, 1) x (1, 0, 0) in component "front left tab 1-2 socket screw"
  circle A0 centre (182.45, 296.75) radius 3.9624
extrude "Join 2'''" add sketch "Join stock profile (4)" along normal blind 4.826 bodies 158 in component "front left tab 1-2 socket screw"
ref_plane "WorkPlane3" through (0, 0, 60.7278) normal (0, 0, 1) x (1, 0, 0) in component "front left tab 1-2 socket screw"
sketch "Cut stock profile (28)" plane through (0, 0, 60.7278) normal (0, 0, 1) x (1, 0, 0) in component "front left tab 1-2 socket screw"
  line L0 (184.7414, 296.75) -> (183.5957, 298.7344)
  line L1 (183.5957, 298.7344) -> (181.3043, 298.7344)
  line L2 (181.3043, 298.7344) -> (180.1586, 296.75)
  line L3 (180.1586, 296.75) -> (181.3043, 294.7656)
  line L4 (181.3043, 294.7656) -> (183.5957, 294.7656)
  line L5 (183.5957, 294.7656) -> (184.7414, 296.75)
extrude "Cut 3'''''''''''" cut sketch "Cut stock profile (28)" along normal blind 2.296 bodies 158 in component "front left tab 1-2 socket screw"
ref_plane "WorkPlane1" through (0, 0, 124.3125) normal (0, 0, 1) x (1, 0, 0) in component "front left tab 1-2 locknut"
sketch "New stock profile (33)" plane through (0, 0, 124.3125) normal (0, 0, 1) x (1, 0, 0) in component "front left tab 1-2 locknut"
  line L0 (187.9639, 296.75) -> (185.207, 301.5252)
  line L1 (185.207, 301.5252) -> (179.693, 301.5252)
  line L2 (179.693, 301.5252) -> (176.9361, 296.75)
  line L3 (176.9361, 296.75) -> (179.693, 291.9748)
  line L4 (179.693, 291.9748) -> (185.207, 291.9748)
  line L5 (185.207, 291.9748) -> (187.9639, 296.75)
  circle A0 centre (182.45, 296.75) radius 2.43
extrude "New 1''''''''''''''''''''''''''''''''" add sketch "New stock profile (33)" along normal blind 6.3246 separate body makes body 159 in component "front left tab 1-2 locknut"
ref_plane "WorkPlane1" through (330.6, 0, 0) normal (1, 0, 0) x (0, 1, 0) in component "front left rail mount 2-1 weld boss"
sketch "New stock profile (34)" plane through (330.6, 0, 0) normal (1, 0, 0) x (0, 0, -1) in component "front left rail mount 2-1 weld boss"
  circle A0 centre (-84.1, 195.15) radius 6.5
  circle A1 centre (-84.1, 195.15) radius 2.5
extrude "New 1'''''''''''''''''''''''''''''''''" add sketch "New stock profile (34)" against normal blind 16 separate body makes body 160 in component "front left rail mount 2-1 weld boss"
ref_plane "WorkPlane1" through (328.5, 0, 0) normal (1, 0, 0) x (0, 1, 0) in component "front left rail mount 2-1 M6 cap screw"
sketch "New stock profile (35)" plane through (328.5, 0, 0) normal (1, 0, 0) x (0, 0, -1) in component "front left rail mount 2-1 M6 cap screw"
  circle A0 centre (-84.1, 195.15) radius 3
extrude "New 1''''''''''''''''''''''''''''''''''" add sketch "New stock profile (35)" against normal blind 40 separate body makes body 161 in component "front left rail mount 2-1 M6 cap screw"
ref_plane "WorkPlane2" through (288.5, 0, 0) normal (1, 0, 0) x (0, 1, 0) in component "front left rail mount 2-1 M6 cap screw"
sketch "Join stock profile (5)" plane through (288.5, 0, 0) normal (1, 0, 0) x (0, 0, -1) in component "front left rail mount 2-1 M6 cap screw"
  circle A0 centre (-84.1, 195.15) radius 5
extrude "Join 2''''" add sketch "Join stock profile (5)" against normal blind 6 bodies 161 in component "front left rail mount 2-1 M6 cap screw"
ref_plane "WorkPlane3" through (282.49, 0, 0) normal (1, 0, 0) x (0, 1, 0) in component "front left rail mount 2-1 M6 cap screw"
sketch "Cut stock profile (29)" plane through (282.49, 0, 0) normal (1, 0, 0) x (0, 0, -1) in component "front left rail mount 2-1 M6 cap screw"
  line L0 (-84.1, 198.0368) -> (-86.6, 196.5934)
  line L1 (-86.6, 196.5934) -> (-86.6, 193.7066)
  line L2 (-86.6, 193.7066) -> (-84.1, 192.2632)
  line L3 (-84.1, 192.2632) -> (-81.6, 193.7066)
  line L4 (-81.6, 193.7066) -> (-81.6, 196.5934)
  line L5 (-81.6, 196.5934) -> (-84.1, 198.0368)
extrude "Cut 3''''''''''''" cut sketch "Cut stock profile (29)" along normal blind 3.01 bodies 161 in component "front left rail mount 2-1 M6 cap screw"
ref_plane "WorkPlane1" through (330.6, 0, 0) normal (1, 0, 0) x (0, 1, 0) in component "front left rail mount 2-2 weld boss"
sketch "New stock profile (36)" plane through (330.6, 0, 0) normal (1, 0, 0) x (0, 0, -1) in component "front left rail mount 2-2 weld boss"
  circle A0 centre (-105.1, 195.15) radius 6.5
  circle A1 centre (-105.1, 195.15) radius 2.5
extrude "New 1'''''''''''''''''''''''''''''''''''" add sketch "New stock profile (36)" against normal blind 16 separate body makes body 162 in component "front left rail mount 2-2 weld boss"
ref_plane "WorkPlane1" through (328.5, 0, 0) normal (1, 0, 0) x (0, 1, 0) in component "front left rail mount 2-2 M6 cap screw"
sketch "New stock profile (37)" plane through (328.5, 0, 0) normal (1, 0, 0) x (0, 0, -1) in component "front left rail mount 2-2 M6 cap screw"
  circle A0 centre (-105.1, 195.15) radius 3
extrude "New 1''''''''''''''''''''''''''''''''''''" add sketch "New stock profile (37)" against normal blind 40 separate body makes body 163 in component "front left rail mount 2-2 M6 cap screw"
ref_plane "WorkPlane2" through (288.5, 0, 0) normal (1, 0, 0) x (0, 1, 0) in component "front left rail mount 2-2 M6 cap screw"
sketch "Join stock profile (6)" plane through (288.5, 0, 0) normal (1, 0, 0) x (0, 0, -1) in component "front left rail mount 2-2 M6 cap screw"
  circle A0 centre (-105.1, 195.15) radius 5
extrude "Join 2'''''" add sketch "Join stock profile (6)" against normal blind 6 bodies 163 in component "front left rail mount 2-2 M6 cap screw"
ref_plane "WorkPlane3" through (282.49, 0, 0) normal (1, 0, 0) x (0, 1, 0) in component "front left rail mount 2-2 M6 cap screw"
sketch "Cut stock profile (30)" plane through (282.49, 0, 0) normal (1, 0, 0) x (0, 0, -1) in component "front left rail mount 2-2 M6 cap screw"
  line L0 (-105.1, 198.0368) -> (-107.6, 196.5934)
  line L1 (-107.6, 196.5934) -> (-107.6, 193.7066)
  line L2 (-107.6, 193.7066) -> (-105.1, 192.2632)
  line L3 (-105.1, 192.2632) -> (-102.6, 193.7066)
  line L4 (-102.6, 193.7066) -> (-102.6, 196.5934)
  line L5 (-102.6, 196.5934) -> (-105.1, 198.0368)
extrude "Cut 3'''''''''''''" cut sketch "Cut stock profile (30)" along normal blind 3.01 bodies 163 in component "front left rail mount 2-2 M6 cap screw"
ref_plane "WorkPlane1" through (0, 0, 65.5637) normal (0, 0, 1) x (1, 0, 0) in component "front left tab 2-1 socket screw"
sketch "New stock profile (38)" plane through (0, 0, 65.5637) normal (0, 0, 1) x (1, 0, 0) in component "front left tab 2-1 socket screw"
  circle A0 centre (296.75, 207.85) radius 2.413
extrude "New 1'''''''''''''''''''''''''''''''''''''" add sketch "New stock profile (38)" along normal blind 69.85 separate body makes body 164 in component "front left tab 2-1 socket screw"
ref_plane "WorkPlane2" through (0, 0, 60.7378) normal (0, 0, 1) x (1, 0, 0) in component "front left tab 2-1 socket screw"
sketch "Join stock profile (7)" plane through (0, 0, 60.7378) normal (0, 0, 1) x (1, 0, 0) in component "front left tab 2-1 socket screw"
  circle A0 centre (296.75, 207.85) radius 3.9624
extrude "Join 2''''''" add sketch "Join stock profile (7)" along normal blind 4.826 bodies 164 in component "front left tab 2-1 socket screw"
ref_plane "WorkPlane3" through (0, 0, 60.7278) normal (0, 0, 1) x (1, 0, 0) in component "front left tab 2-1 socket screw"
sketch "Cut stock profile (31)" plane through (0, 0, 60.7278) normal (0, 0, 1) x (1, 0, 0) in component "front left tab 2-1 socket screw"
  line L0 (299.0414, 207.85) -> (297.8957, 209.8344)
  line L1 (297.8957, 209.8344) -> (295.6043, 209.8344)
  line L2 (295.6043, 209.8344) -> (294.4586, 207.85)
  line L3 (294.4586, 207.85) -> (295.6043, 205.8656)
  line L4 (295.6043, 205.8656) -> (297.8957, 205.8656)
  line L5 (297.8957, 205.8656) -> (299.0414, 207.85)
extrude "Cut 3''''''''''''''" cut sketch "Cut stock profile (31)" along normal blind 2.296 bodies 164 in component "front left tab 2-1 socket screw"
ref_plane "WorkPlane1" through (0, 0, 124.3125) normal (0, 0, 1) x (1, 0, 0) in component "front left tab 2-1 locknut"
sketch "New stock profile (39)" plane through (0, 0, 124.3125) normal (0, 0, 1) x (1, 0, 0) in component "front left tab 2-1 locknut"
  line L0 (302.2639, 207.85) -> (299.507, 212.6252)
  line L1 (299.507, 212.6252) -> (293.993, 212.6252)
  line L2 (293.993, 212.6252) -> (291.2361, 207.85)
  line L3 (291.2361, 207.85) -> (293.993, 203.0748)
  line L4 (293.993, 203.0748) -> (299.507, 203.0748)
  line L5 (299.507, 203.0748) -> (302.2639, 207.85)
  circle A0 centre (296.75, 207.85) radius 2.43
extrude "New 1''''''''''''''''''''''''''''''''''''''" add sketch "New stock profile (39)" along normal blind 6.3246 separate body makes body 165 in component "front left tab 2-1 locknut"
ref_plane "WorkPlane1" through (0, 0, 65.5637) normal (0, 0, 1) x (1, 0, 0) in component "front left tab 2-2 socket screw"
sketch "New stock profile (40)" plane through (0, 0, 65.5637) normal (0, 0, 1) x (1, 0, 0) in component "front left tab 2-2 socket screw"
  circle A0 centre (296.75, 182.45) radius 2.413
extrude "New 1'''''''''''''''''''''''''''''''''''''''" add sketch "New stock profile (40)" along normal blind 69.85 separate body makes body 166 in component "front left tab 2-2 socket screw"
ref_plane "WorkPlane2" through (0, 0, 60.7378) normal (0, 0, 1) x (1, 0, 0) in component "front left tab 2-2 socket screw"
sketch "Join stock profile (8)" plane through (0, 0, 60.7378) normal (0, 0, 1) x (1, 0, 0) in component "front left tab 2-2 socket screw"
  circle A0 centre (296.75, 182.45) radius 3.9624
extrude "Join 2'''''''" add sketch "Join stock profile (8)" along normal blind 4.826 bodies 166 in component "front left tab 2-2 socket screw"
ref_plane "WorkPlane3" through (0, 0, 60.7278) normal (0, 0, 1) x (1, 0, 0) in component "front left tab 2-2 socket screw"
sketch "Cut stock profile (32)" plane through (0, 0, 60.7278) normal (0, 0, 1) x (1, 0, 0) in component "front left tab 2-2 socket screw"
  line L0 (299.0414, 182.45) -> (297.8957, 184.4344)
  line L1 (297.8957, 184.4344) -> (295.6043, 184.4344)
  line L2 (295.6043, 184.4344) -> (294.4586, 182.45)
  line L3 (294.4586, 182.45) -> (295.6043, 180.4656)
  line L4 (295.6043, 180.4656) -> (297.8957, 180.4656)
  line L5 (297.8957, 180.4656) -> (299.0414, 182.45)
extrude "Cut 3'''''''''''''''" cut sketch "Cut stock profile (32)" along normal blind 2.296 bodies 166 in component "front left tab 2-2 socket screw"
ref_plane "WorkPlane1" through (0, 0, 124.3125) normal (0, 0, 1) x (1, 0, 0) in component "front left tab 2-2 locknut"
sketch "New stock profile (41)" plane through (0, 0, 124.3125) normal (0, 0, 1) x (1, 0, 0) in component "front left tab 2-2 locknut"
  line L0 (302.2639, 182.45) -> (299.507, 187.2252)
  line L1 (299.507, 187.2252) -> (293.993, 187.2252)
  line L2 (293.993, 187.2252) -> (291.2361, 182.45)
  line L3 (291.2361, 182.45) -> (293.993, 177.6748)
  line L4 (293.993, 177.6748) -> (299.507, 177.6748)
  line L5 (299.507, 177.6748) -> (302.2639, 182.45)
  circle A0 centre (296.75, 182.45) radius 2.43
extrude "New 1''''''''''''''''''''''''''''''''''''''''" add sketch "New stock profile (41)" along normal blind 6.3246 separate body makes body 167 in component "front left tab 2-2 locknut"
ref_plane "WorkPlane1" through (330.6, 0, 0) normal (1, 0, 0) x (0, 1, 0) in component "front right rail mount 1-1 weld boss"
sketch "New stock profile (42)" plane through (330.6, 0, 0) normal (1, 0, 0) x (0, 0, -1) in component "front right rail mount 1-1 weld boss"
  circle A0 centre (-84.1, -195.15) radius 6.5
  circle A1 centre (-84.1, -195.15) radius 2.5
extrude "New 1'''''''''''''''''''''''''''''''''''''''''" add sketch "New stock profile (42)" against normal blind 16 separate body makes body 168 in component "front right rail mount 1-1 weld boss"
ref_plane "WorkPlane1" through (328.5, 0, 0) normal (1, 0, 0) x (0, 1, 0) in component "front right rail mount 1-1 M6 cap screw"
sketch "New stock profile (43)" plane through (328.5, 0, 0) normal (1, 0, 0) x (0, 0, -1) in component "front right rail mount 1-1 M6 cap screw"
  circle A0 centre (-84.1, -195.15) radius 3
extrude "New 1''''''''''''''''''''''''''''''''''''''''''" add sketch "New stock profile (43)" against normal blind 40 separate body makes body 169 in component "front right rail mount 1-1 M6 cap screw"
ref_plane "WorkPlane2" through (288.5, 0, 0) normal (1, 0, 0) x (0, 1, 0) in component "front right rail mount 1-1 M6 cap screw"